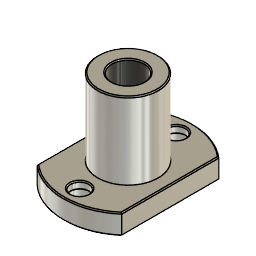
Mini 3D Scanner - Mark 2 (Autodesk Fusion 360 archive; units mm, degrees)
design "Linear Motion Bearing (8mm)"
Autodesk Fusion 360 part; units mm, degrees
sketch "Sketch1" plane through (0, 0, 0) normal (0, 0, 1) x (1, 0, 0)
  circle A0 centre (0, 0) radius 4
  circle A1 centre (0, 0) radius 7.5
  line L0 (0, 0) -> (10.5, 0) construction
  line L1 (0, 0) -> (-10.5, 0) construction
  line L2 (-10.5, 0) -> (-10.5, 12.0727)
  line L3 (-10.5, 0) -> (-10.5, -12.0727)
  line L4 (10.5, 0) -> (10.5, -12.0727)
  line L5 (10.5, 0) -> (10.5, 12.0727)
  circle A2 centre (0, 12) radius 3
  circle A3 centre (0, 12) radius 2.25
  circle A4 centre (0, -12) radius 3
  circle A5 centre (0, -12) radius 2.25
  arc A6 (10.5, 12.0727) -> (-10.5, 12.0727) centre (0, 0) ccw
  arc A7 (-10.5, -12.0727) -> (10.5, -12.0727) centre (0, 0) ccw
  dimension "d1" = 8
  dimension "d2" = 15
  dimension "d3" = 32
  dimension "d4" = 10.5
  dimension "d5" = 10.5
  dimension "d6" = 6
  dimension "d7" = 12
  dimension "d8" = 4.5
  constraint coincident A0.centre A1.centre
  constraint concentric A1 A6
  constraint horizontal L0
  constraint parallel L0 L1
  constraint perpendicular L1 L2
  constraint perpendicular L1 L3
  constraint perpendicular L0 L4
  constraint perpendicular L0 L5
  constraint concentric A2 A3
  constraint symmetric L0 A2 A4
  constraint symmetric L0 A3 A5
  constraint concentric A6 A7
  measures "d1" diameter of A0
  measures "d2" diameter of A1
  measures "d3" diameter of A6
  measures "d4" distance of A0.centre L0.end
  measures "d5" distance of A0.centre L1.end
  measures "d6" diameter of A2
  measures "d7" distance of A0.centre A2.centre
  measures "d8" diameter of A3
extrude "Extrude1" add sketch "Sketch1" along normal blind 24 contours A1
extrude "Extrude2" add sketch "Sketch1" along normal blind 5 contours L2 L3 L4 L5 A6 A7 | A2 | A4
extrude "Extrude3" cut sketch "Sketch1" along normal blind 3.1 contours A2 | A4
chamfer "Chamfer1" distance 0.25 angle 45 16 edges at (-2.797, 10.9152, 0) (0, 16, 0) (-10.5, 0, 0) (10.5, 0, 0) (0, -16, 0) (-2.797, -13.0848, 0) (10.5, 0, 5) (0, 16, 5) (-10.5, 0, 5) (0, -16, 5) (-2.0977, -11.1864, 3.1) (-2.0977, 12.8136, 3.1) (-6.9925, -2.7121, 24) (-3.7293, 1.4465, 24) (-2.0977, -11.1864, 5) (-2.0977, 12.8136, 5) tangent chain off
extrude "Extrude4" cut sketch "Sketch1" along normal blind 0.25 contours A1
equation "d4 = ( 21 / 2 ) * 1 mm"
equation "d5 = ( 21 / 2 ) * 1 mm"
equation "d7 = ( 24 / 2 ) * 1 mm"

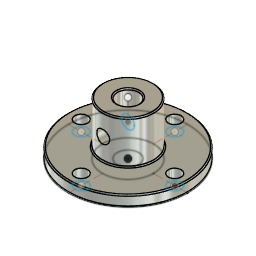
design "Coupling Flange (5mm)"
Autodesk Fusion 360 part; units mm, degrees
sketch "Sketch1" plane through (0, 0, 0) normal (0, 0, 1) x (1, 0, 0)
  circle A0 centre (0, 0) radius 2.5
  circle A1 centre (0, 0) radius 6
  circle A2 centre (0, 0) radius 14
  line L0 (-14, 0) -> (-6, 0) construction
  line L1 (0, 6) -> (0, 14) construction
  line L2 (6, 0) -> (14, 0) construction
  line L3 (0, -6) -> (0, -14) construction
  circle A3 centre (11, 0) radius 1.5
  circle A4 centre (0, 11) radius 1.5
  circle A5 centre (-11, 0) radius 1.5
  circle A6 centre (0, -11) radius 1.5
  point P0 (11, 0)
  dimension "d1" = 5
  dimension "d2" = 12
  dimension "d3" = 28
  dimension "d24" = 11
  dimension "d25" = 3
  dimension "d27" = 360
  constraint coincident A0.centre A1.centre
  constraint concentric A1 A2
  constraint coincident A2 L0.start
  constraint coincident A1 L0.end
  constraint horizontal L0
  constraint coincident A1 L1.start
  constraint coincident A2 L1.end
  constraint perpendicular L0 L1
  constraint coincident A1 L2.start
  constraint coincident A2 L2.end
  constraint perpendicular L1 L2
  constraint coincident A1 L3.start
  constraint coincident A2 L3.end
  constraint perpendicular L2 L3
  constraint coincident L2 P0
  constraint coincident P0 A3.centre
  measures "d1" diameter of A0
  measures "d2" diameter of A1
  measures "d3" diameter of A2
  measures "d24" distance of A0.centre P0
  measures "d25" diameter of A3
extrude "Extrude1" add sketch "Sketch1" along normal blind 12.5 contours A1
extrude "Extrude2" add sketch "Sketch1" along normal blind 2.5 contours A2 | A3 | A4 | A5 | A6
fillet "Fillet1" radius 0.25 6 edges at (-5.594, -2.1697, 12.5) (-2.3308, 0.904, 12.5) (-5.594, -2.1697, 2.5) (-13.0526, -5.0626, 2.5) (-13.0526, -5.0626, 0) (-2.3308, 0.904, 0)
sketch "Sketch2" plane through (0, 0, 0) normal (0, 1, 0) x (1, 0, 0)
  line L0 (0, -12.5) -> (0, -7.5) construction
  circle A0 centre (0, -7.5) radius 1.5
  dimension "d20" = 5
  dimension "d21" = 3
  constraint vertical L0
  constraint coincident L0.end A0.centre
  measures "d20" distance of L0.start L0.end
  measures "d21" diameter of A0
extrude "Extrude3" cut sketch "Sketch2" along normal mid plane 14
extrude "Extrude4" cut sketch "Sketch1" along normal blind 4 contours A3 | A4 | A5 | A6
equation "d20 = 3.5 mm + ( 3 / 2 ) * 1 mm"
equation "d24 = 12.5 mm - ( 3 / 2 ) * 1 mm"
